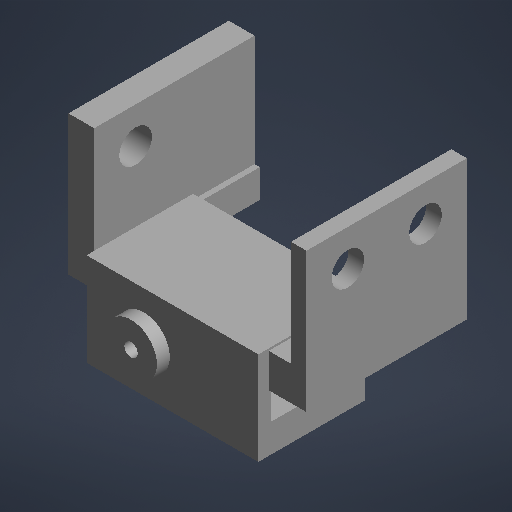
# Autodesk Inventor part: R2_tobillo_izq
Saved by Autodesk Inventor 2027 (Build 310192060, 192F)
## iProperties
Part Number: R2_tobillo_izq
Material: Genérico
Document SubType Name: Modelado
Designer: rodri
Appearance: Por defecto
Author: rodri
Autodesk Inventor part; units mm, degrees
ref_plane "Plano de trabajo1" through (0, 0, -3.1) normal (0, 0, 1) x (1, 0, 0)
sketch "Boceto1" plane through (0, 0, -3.1) normal (0, 0, 1) x (1, 0, 0)
  line L0 (12.9, -153) -> (46.1, -153)
  line L1 (46.1, -153) -> (46.1, -135)
  line L2 (46.1, -135) -> (12.9, -135)
  line L3 (12.9, -135) -> (12.9, -153)
  constraints: 8 end point, 2 parallel, 1 horizontal, 1 perpendicular
extrude "Extrusión1" add sketch "Boceto1" along normal blind 20.6
ref_plane "Plano de trabajo2" through (0, 0, -3.2) normal (0, 0, 1) x (1, 0, 0)
sketch "Boceto2" plane through (0, 0, -3.2) normal (0, 0, 1) x (1, 0, 0)
  line L0 (17.7, -150.5) -> (41.3, -150.5)
  line L1 (41.3, -150.5) -> (41.3, -137.5)
  line L2 (41.3, -137.5) -> (17.7, -137.5)
  line L3 (17.7, -137.5) -> (17.7, -150.5)
  constraints: 8 end point, 2 parallel, 1 horizontal, 1 perpendicular
extrude "Extrusión2" cut sketch "Boceto2" along normal blind 18.2
ref_plane "Plano de trabajo3" through (0, 0, 10) normal (0, 0, 1) x (1, 0, 0)
sketch "Boceto3" plane through (0, 0, 10) normal (0, 0, 1) x (1, 0, 0)
  line L0 (39.5, -147.5) -> (46.5, -147.5)
  line L1 (46.5, -147.5) -> (46.5, -140.5)
  line L2 (46.5, -140.5) -> (39.5, -140.5)
  line L3 (39.5, -140.5) -> (39.5, -147.5)
  constraints: 8 end point, 2 parallel, 1 horizontal, 1 perpendicular
extrude "Extrusión3" cut sketch "Boceto3" along normal blind 5
ref_plane "Plano de trabajo4" through (0, 0, -3.2) normal (0, 0, 1) x (1, 0, 0)
sketch "Boceto4" plane through (0, 0, -3.2) normal (0, 0, 1) x (1, 0, 0)
  circle A0 centre (43.4, -144) radius 0.85
  constraints: 1 centre point
extrude "Extrusión4" cut sketch "Boceto4" along normal blind 6.1
ref_plane "Plano de trabajo5" through (0, 0, -3.2) normal (0, 0, 1) x (1, 0, 0)
sketch "Boceto5" plane through (0, 0, -3.2) normal (0, 0, 1) x (1, 0, 0)
  circle A0 centre (15.6, -144) radius 0.85
  constraints: 1 centre point
extrude "Extrusión5" cut sketch "Boceto5" along normal blind 6.1
ref_plane "Plano de trabajo6" through (0, 0, 17.49) normal (0, 0, 1) x (1, 0, 0)
sketch "Boceto6" plane through (0, 0, 17.49) normal (0, 0, 1) x (1, 0, 0)
  circle A0 centre (24, -144) radius 5
  constraints: 1 centre point
extrude "Extrusión6" add sketch "Boceto6" along normal blind 2.51
ref_plane "Plano de trabajo7" through (0, 0, 15.6) normal (0, 0, 1) x (1, 0, 0)
sketch "Boceto7" plane through (0, 0, 15.6) normal (0, 0, 1) x (1, 0, 0)
  circle A0 centre (24, -144) radius 1.3
  constraints: 1 centre point
extrude "Extrusión7" cut sketch "Boceto7" along normal blind 4.5
ref_plane "Plano de trabajo8" through (0, 0, -15.5) normal (0, 0, 1) x (1, 0, 0)
sketch "Boceto8" plane through (0, 0, -15.5) normal (0, 0, 1) x (1, 0, 0)
  line L0 (7.4, -142) -> (12.39, -142)
  line L1 (12.39, -142) -> (12.39, -115)
  line L2 (12.39, -115) -> (7.4, -115)
  line L3 (7.4, -115) -> (7.4, -142)
  constraints: 8 end point, 2 parallel, 1 horizontal, 1 perpendicular
extrude "Extrusión8" add sketch "Boceto8" along normal blind 31
ref_plane "Plano de trabajo9" through (7.4, 0, 0) normal (1, 0, 0) x (0, 1, 0)
sketch "Boceto9" plane through (7.4, 0, 0) normal (1, 0, 0) x (0, 1, 0)
  circle A0 centre (-122, -7.5) radius 7
  constraints: 1 centre point
extrude "Extrusión9" add sketch "Boceto9" along normal blind 4.99
ref_plane "Plano de trabajo10" through (7.4, 0, 0) normal (1, 0, 0) x (0, 1, 0)
sketch "Boceto10" plane through (7.4, 0, 0) normal (1, 0, 0) x (0, 1, 0)
  circle A0 centre (-122, 7.5) radius 7
  constraints: 1 centre point
extrude "Extrusión10" add sketch "Boceto10" along normal blind 4.99
ref_plane "Plano de trabajo11" through (0, 0, -15.5) normal (0, 0, 1) x (1, 0, 0)
sketch "Boceto11" plane through (0, 0, -15.5) normal (0, 0, 1) x (1, 0, 0)
  line L0 (50.41, -142) -> (53.41, -142)
  line L1 (53.41, -142) -> (53.41, -115)
  line L2 (53.41, -115) -> (50.41, -115)
  line L3 (50.41, -115) -> (50.41, -142)
  constraints: 8 end point, 2 parallel, 1 horizontal, 1 perpendicular
extrude "Extrusión11" add sketch "Boceto11" along normal blind 31
ref_plane "Plano de trabajo12" through (50.41, 0, 0) normal (1, 0, 0) x (0, 1, 0)
sketch "Boceto12" plane through (50.41, 0, 0) normal (1, 0, 0) x (0, 1, 0)
  circle A0 centre (-122, -7.5) radius 7
  constraints: 1 centre point
extrude "Extrusión12" add sketch "Boceto12" along normal blind 3
ref_plane "Plano de trabajo13" through (50.41, 0, 0) normal (1, 0, 0) x (0, 1, 0)
sketch "Boceto13" plane through (50.41, 0, 0) normal (1, 0, 0) x (0, 1, 0)
  circle A0 centre (-122, 7.5) radius 7
  constraints: 1 centre point
extrude "Extrusión13" add sketch "Boceto13" along normal blind 3
ref_plane "Plano de trabajo14" through (0, 0, -15.5) normal (0, 0, 1) x (1, 0, 0)
sketch "Boceto14" plane through (0, 0, -15.5) normal (0, 0, 1) x (1, 0, 0)
  line L0 (46.1, -142) -> (53.4, -142)
  line L1 (53.4, -142) -> (53.4, -135.4)
  line L2 (53.4, -135.4) -> (46.1, -135.4)
  line L3 (46.1, -135.4) -> (46.1, -142)
  constraints: 8 end point, 2 parallel, 1 horizontal, 1 perpendicular
extrude "Extrusión14" add sketch "Boceto14" along normal blind 31
ref_plane "Plano de trabajo15" through (0, 0, -15.5) normal (0, 0, 1) x (1, 0, 0)
sketch "Boceto15" plane through (0, 0, -15.5) normal (0, 0, 1) x (1, 0, 0)
  line L0 (7.4, -142) -> (13.4, -142)
  line L1 (13.4, -142) -> (13.4, -136.5)
  line L2 (13.4, -136.5) -> (7.4, -136.5)
  line L3 (7.4, -136.5) -> (7.4, -142)
  constraints: 8 end point, 2 parallel, 1 horizontal, 1 perpendicular
extrude "Extrusión15" add sketch "Boceto15" along normal blind 31
ref_plane "Plano de trabajo16" through (7.3, 0, 0) normal (1, 0, 0) x (0, 1, 0)
sketch "Boceto16" plane through (7.3, 0, 0) normal (1, 0, 0) x (0, 1, 0)
  circle A0 centre (-122, 7.5) radius 3.15
  constraints: 1 centre point
extrude "Extrusión16" cut sketch "Boceto16" along normal blind 5.2
ref_plane "Plano de trabajo17" through (50.3, 0, 0) normal (1, 0, 0) x (0, 1, 0)
sketch "Boceto17" plane through (50.3, 0, 0) normal (1, 0, 0) x (0, 1, 0)
  circle A0 centre (-122, 7.5) radius 3.15
  constraints: 1 centre point
extrude "Extrusión17" cut sketch "Boceto17" along normal blind 3.3
ref_plane "Plano de trabajo18" through (7.3, 0, 0) normal (1, 0, 0) x (0, 1, 0)
sketch "Boceto18" plane through (7.3, 0, 0) normal (1, 0, 0) x (0, 1, 0)
  circle A0 centre (-122, -7.5) radius 4.2
  constraints: 1 centre point
extrude "Extrusión18" cut sketch "Boceto18" along normal blind 3.2
ref_plane "Plano de trabajo19" through (50.3, 0, 0) normal (1, 0, 0) x (0, 1, 0)
sketch "Boceto19" plane through (50.3, 0, 0) normal (1, 0, 0) x (0, 1, 0)
  circle A0 centre (-122, -7.5) radius 3.15
  constraints: 1 centre point
extrude "Extrusión19" cut sketch "Boceto19" along normal blind 3.3
